Autodesk Fusion 360 part; units mm, degrees
(part 2 of 2)
sketch "Sketch1" plane through (0, 0, 0) normal (0, 0, 1) x (1, 0, 0)
  line L0 (0, 0) -> (490, 0)
  line L1 (490, 0) -> (490, -745)
  line L2 (490, -745) -> (0, -745)
  line L3 (0, -745) -> (0, 0)
  line L4 (7.5, -7.5) -> (482.5, -7.5) construction
  line L5 (482.5, -7.5) -> (482.5, -737.5) construction
  line L6 (482.5, -737.5) -> (7.5, -737.5) construction
  line L7 (7.5, -737.5) -> (7.5, -7.5) construction
  line L8 (0, -50) -> (490, -50) construction
  line L9 (0, -695) -> (490, -695) construction
  line L10 (0, -157.5) -> (490, -157.5) construction
  line L11 (0, -265) -> (490, -265) construction
  line L12 (0, -372.5) -> (490, -372.5) construction
  line L13 (50, 0) -> (50, -745) construction
  line L14 (440, 0) -> (440, -745) construction
  line L15 (147.5, 0) -> (147.5, -745) construction
  line L16 (245, 0) -> (245, -745) construction
  line L17 (342.5, 0) -> (342.5, -745) construction
  circle A0 centre (50, -737.5) radius 1.75
  circle A1 centre (147.5, -737.5) radius 1.75
  circle A2 centre (245, -737.5) radius 1.75
  circle A3 centre (342.5, -737.5) radius 1.75
  circle A4 centre (440, -737.5) radius 1.75
  circle A5 centre (7.5, -695) radius 1.75
  circle A6 centre (7.5, -372.5) radius 1.75
  circle A7 centre (7.5, -372.5) radius 1.75
  circle A8 centre (7.5, -157.5) radius 1.75
  circle A9 centre (7.5, -50) radius 1.75
  circle A10 centre (50, -7.5) radius 1.75
  circle A11 centre (147.5, -7.5) radius 1.75
  circle A12 centre (245, -7.5) radius 1.75
  circle A13 centre (342.5, -7.5) radius 1.75
  circle A14 centre (440, -7.5) radius 1.75
  circle A15 centre (482.5, -50) radius 1.75
  circle A16 centre (482.5, -157.5) radius 1.75
  circle A17 centre (482.5, -372.5) radius 1.75
  circle A18 centre (482.5, -372.5) radius 1.75
  circle A19 centre (482.5, -695) radius 1.75
  line L18 (0, -480) -> (490, -480) construction
  line L19 (0, -587.5) -> (490, -587.5) construction
  circle A20 centre (7.5, -480) radius 1.75
  circle A21 centre (7.5, -587.5) radius 1.75
  circle A22 centre (482.5, -480) radius 1.75
  circle A23 centre (482.5, -587.5) radius 1.75
  circle A24 centre (7.5, -265) radius 1.75
  circle A25 centre (482.5, -265) radius 1.75
  dimension "d1" = 745
  dimension "d2" = 490
  dimension "d3" = 7.5
  dimension "d4" = 7.5
  dimension "d5" = 7.5
  dimension "d6" = 7.5
  dimension "d9" = 50
  dimension "d10" = 50
  dimension "d11" = 107.5
  dimension "d12" = 107.5
  dimension "d13" = 107.5
  dimension "d14" = 50
  dimension "d15" = 50
  dimension "d16" = 97.5
  dimension "d17" = 97.5
  dimension "d18" = 97.5
  dimension "d20" = 3.5
  dimension "d21" = 3.5
  dimension "d22" = 3.5
  dimension "d23" = 3.5
  dimension "d24" = 3.5
  dimension "d25" = 3.5
  dimension "d26" = 3.5
  dimension "d27" = 3.5
  dimension "d28" = 3.5
  dimension "d29" = 3.5
  dimension "d30" = 3.5
  dimension "d31" = 3.5
  dimension "d32" = 3.5
  dimension "d33" = 3.5
  dimension "d34" = 3.5
  dimension "d35" = 3.5
  dimension "d36" = 3.5
  dimension "d37" = 3.5
  dimension "d38" = 3.5
  dimension "d39" = 3.5
  dimension "d57" = 107.5
  dimension "d58" = 107.5
  dimension "d59" = 3.5
  dimension "d60" = 3.5
  dimension "d61" = 3.5
  dimension "d62" = 3.5
  dimension "d63" = 3.5
  dimension "d64" = 3.5
  measures "d1" distance of L0.start L2.end
  measures "d2" distance of L0.start L0.end
  measures "d3" distance of L3 L7
  measures "d4" distance of L2 L6
  measures "d5" distance of L0 L4
  measures "d6" distance of L1 L5
  measures "d9" distance of L0 L8
  measures "d10" distance of L2 L9
  measures "d11" distance of L8 L10
  measures "d12" distance of L10 L11
  measures "d13" distance of L11 L12
  measures "d14" distance of L3 L13
  measures "d15" distance of L1 L14
  measures "d16" distance of L13 L15
  measures "d17" distance of L15 L16
  measures "d18" distance of L16 L17
  measures "d20" diameter of A0
  measures "d21" diameter of A1
  measures "d22" diameter of A2
  measures "d23" diameter of A3
  measures "d24" diameter of A4
  measures "d25" diameter of A5
  measures "d26" diameter of A6
  measures "d27" diameter of A7
  measures "d28" diameter of A8
  measures "d29" diameter of A9
  measures "d30" diameter of A10
  measures "d31" diameter of A11
  measures "d32" diameter of A12
  measures "d33" diameter of A13
  measures "d34" diameter of A14
  measures "d35" diameter of A15
  measures "d36" diameter of A16
  measures "d37" diameter of A17
  measures "d38" diameter of A18
  measures "d39" diameter of A19
  measures "d57" distance of L12 L18
  measures "d58" distance of L18 L19
  measures "d59" diameter of A20
  measures "d60" diameter of A21
  measures "d61" diameter of A22
  measures "d62" diameter of A23
  measures "d63" diameter of A24
  measures "d64" diameter of A25
extrude "Extrude1" add sketch "Sketch1" along normal blind 6.35
fillet "Fillet1" radius 5 4 edges at (490, -745, 3.175) (0, -745, 3.175) (0, 0, 3.175) (490, 0, 3.175)
sketch "Sketch2" plane through (0, 0, 6.35) normal (0, 0, 1) x (-1, 0, 0)
  arc A0 (-490, 5) -> (-485, 0) centre (-485, 5) ccw
  line L0 (-485, 0) -> (-5, 0)
  arc A1 (-5, 0) -> (0, 5) centre (-5, 5) ccw
  line L1 (0, 5) -> (0, 740)
  arc A2 (0, 740) -> (-5, 745) centre (-5, 740) ccw
  line L2 (-5, 745) -> (-485, 745)
  arc A3 (-485, 745) -> (-490, 740) centre (-485, 740) ccw
  line L3 (-490, 740) -> (-490, 5)
  circle A4 centre (-482.5, 50) radius 1.75
  circle A5 centre (-482.5, 695) radius 1.75
  circle A6 centre (-147.5, 7.5) radius 1.75
  circle A7 centre (-7.5, 157.5) radius 1.75
  circle A8 centre (-342.5, 737.5) radius 1.75
  circle A9 centre (-50, 7.5) radius 1.75
  circle A10 centre (-7.5, 372.5) radius 1.75
  circle A11 centre (-440, 737.5) radius 1.75
  circle A12 centre (-482.5, 157.5) radius 1.75
  circle A13 centre (-245, 737.5) radius 1.75
  circle A14 centre (-50, 737.5) radius 1.75
  circle A15 centre (-482.5, 372.5) radius 1.75
  circle A16 centre (-7.5, 695) radius 1.75
  circle A17 centre (-342.5, 7.5) radius 1.75
  circle A18 centre (-7.5, 50) radius 1.75
  circle A19 centre (-440, 7.5) radius 1.75
  circle A20 centre (-245, 7.5) radius 1.75
  circle A21 centre (-147.5, 737.5) radius 1.75
  line L4 (-40, 50) -> (-450, 50)
  line L5 (-450, 50) -> (-450, 695)
  line L6 (-450, 695) -> (-40, 695)
  line L7 (-40, 695) -> (-40, 50)
  circle A22 centre (-7.5, 480) radius 1.75
  circle A23 centre (-7.5, 587.5) radius 1.75
  circle A24 centre (-482.5, 480) radius 1.75
  circle A25 centre (-482.5, 587.5) radius 1.75
  circle A26 centre (-482.5, 265) radius 1.75
  circle A27 centre (-7.5, 265) radius 1.75
  dimension "d50" = 40
  dimension "d51" = 50
  dimension "d52" = 40
  dimension "d53" = 50
  measures "d50" distance of L1 L7
  measures "d51" distance of L2 L6
  measures "d52" distance of L3 L5
  measures "d53" distance of L0 L4
extrude "Extrude2" cut sketch "Sketch2" against normal up to surface (6.35 mm away) contours L4 L5 L6 L7
fillet "Fillet2" radius 10 4 edges at (40, -50, 3.175) (450, -50, 3.175) (450, -695, 3.175) (40, -695, 3.175)
equation "d1 = YDepth"
equation "d2 = XWidth"
equation "d3 = HoleOffset"
equation "d4 = HoleOffset"
equation "d5 = HoleOffset"
equation "d6 = HoleOffset"
equation "HoleOffset = 7.5 mm"
equation "Diameter = 3.5 mm"
equation "d9 = EdgeToFirstHole"
equation "d10 = EdgeToFirstHole"
equation "d11 = YSpacing"
equation "d12 = YSpacing"
equation "d13 = YSpacing"
equation "d14 = EdgeToFirstHole"
equation "d15 = EdgeToFirstHole"
equation "d16 = XSpacing"
equation "d17 = XSpacing"
equation "d18 = XSpacing"
equation "d20 = Diameter"
equation "d21 = Diameter"
equation "d22 = Diameter"
equation "d23 = Diameter"
equation "d24 = Diameter"
equation "d25 = Diameter"
equation "d26 = Diameter"
equation "d27 = Diameter"
equation "d28 = Diameter"
equation "d29 = Diameter"
equation "d30 = Diameter"
equation "d31 = Diameter"
equation "d32 = Diameter"
equation "d33 = Diameter"
equation "d34 = Diameter"
equation "d35 = Diameter"
equation "d36 = Diameter"
equation "d37 = Diameter"
equation "d38 = Diameter"
equation "d39 = Diameter"
equation "EdgeToFirstHole = 50 mm"
equation "YDepth = 745 mm"
equation "XWidth = 490 mm"
equation "YSpacing = ( YDepth - ( 2 * EdgeToFirstHole ) ) / 6"
equation "XSpacing = ( XWidth - ( 2 * EdgeToFirstHole ) ) / 4"
equation "thickness = 0.25 in"
equation "d47 = thickness"
equation "d57 = YSpacing"
equation "d58 = YSpacing"
equation "d59 = Diameter"
equation "d60 = Diameter"
equation "d61 = Diameter"
equation "d62 = Diameter"
equation "d63 = Diameter"
equation "d64 = Diameter"
